Autodesk Fusion 360 part; units mm, degrees
(part 2 of 2)
sketch "Yellow connector plug sketch" plane through (0, 0, 3) normal (0, 0, 1) x (1, 0, 0) in component "14 Temperature sensor | Illustrative placement; probe detail pending"
  line L0 (102, 70) -> (114, 70)
  line L1 (114, 70) -> (114, 90)
  line L2 (114, 90) -> (102, 90)
  line L3 (102, 90) -> (102, 70)
extrude "Yellow connector plug" add sketch "Yellow connector plug sketch" along normal blind 6 separate body makes body 36 in component "14 Temperature sensor | Illustrative placement; probe detail pending"
ref_plane "WorkPlane5" through (0, 0, 4.5) normal (0, 0, 1) x (1, 0, 0) in component "14 Temperature sensor | Illustrative placement; probe detail pending"
sketch "Spade prongs sketch" plane through (0, 0, 4.5) normal (0, 0, 1) x (1, 0, 0) in component "14 Temperature sensor | Illustrative placement; probe detail pending"
  line L0 (104, 90) -> (106, 90)
  line L1 (106, 90) -> (106, 98)
  line L2 (106, 98) -> (104, 98)
  line L3 (104, 98) -> (104, 90)
  line L4 (110, 90) -> (112, 90)
  line L5 (112, 90) -> (112, 98)
  line L6 (112, 98) -> (110, 98)
  line L7 (110, 98) -> (110, 90)
extrude "Spade prongs" add sketch "Spade prongs sketch" along normal blind 3 bodies 36 in component "14 Temperature sensor | Illustrative placement; probe detail pending"
ref_plane "WorkPlane1" through (0, 0, -6.5) normal (0, 0, 1) x (1, 0, 0) in component "15 Lab test bench elevation standoffs & feet"
sketch "Leg_6_6 sketch" plane through (0, 0, -6.5) normal (0, 0, 1) x (1, 0, 0) in component "15 Lab test bench elevation standoffs & feet"
  circle A0 centre (6, 6) radius 4
extrude "Leg_6_6" add sketch "Leg_6_6 sketch" against normal blind 16 separate body makes body 37 in component "15 Lab test bench elevation standoffs & feet"
ref_plane "WorkPlane2" through (0, 0, -22.5) normal (0, 0, 1) x (1, 0, 0) in component "15 Lab test bench elevation standoffs & feet"
sketch "Foot_6_6 sketch" plane through (0, 0, -22.5) normal (0, 0, 1) x (1, 0, 0) in component "15 Lab test bench elevation standoffs & feet"
  circle A0 centre (6, 6) radius 6
extrude "Foot_6_6" add sketch "Foot_6_6 sketch" against normal blind 3 bodies 37 in component "15 Lab test bench elevation standoffs & feet"
ref_plane "WorkPlane3" through (0, 0, -6.5) normal (0, 0, 1) x (1, 0, 0) in component "15 Lab test bench elevation standoffs & feet"
sketch "Leg_74_6 sketch" plane through (0, 0, -6.5) normal (0, 0, 1) x (1, 0, 0) in component "15 Lab test bench elevation standoffs & feet"
  circle A0 centre (74, 6) radius 4
extrude "Leg_74_6" add sketch "Leg_74_6 sketch" against normal blind 16 separate body makes body 38 in component "15 Lab test bench elevation standoffs & feet"
ref_plane "WorkPlane4" through (0, 0, -22.5) normal (0, 0, 1) x (1, 0, 0) in component "15 Lab test bench elevation standoffs & feet"
sketch "Foot_74_6 sketch" plane through (0, 0, -22.5) normal (0, 0, 1) x (1, 0, 0) in component "15 Lab test bench elevation standoffs & feet"
  circle A0 centre (74, 6) radius 6
extrude "Foot_74_6" add sketch "Foot_74_6 sketch" against normal blind 3 bodies 38 in component "15 Lab test bench elevation standoffs & feet"
ref_plane "WorkPlane5" through (0, 0, -6.5) normal (0, 0, 1) x (1, 0, 0) in component "15 Lab test bench elevation standoffs & feet"
sketch "Leg_6_114 sketch" plane through (0, 0, -6.5) normal (0, 0, 1) x (1, 0, 0) in component "15 Lab test bench elevation standoffs & feet"
  circle A0 centre (6, 114) radius 4
extrude "Leg_6_114" add sketch "Leg_6_114 sketch" against normal blind 16 separate body makes body 39 in component "15 Lab test bench elevation standoffs & feet"
ref_plane "WorkPlane6" through (0, 0, -22.5) normal (0, 0, 1) x (1, 0, 0) in component "15 Lab test bench elevation standoffs & feet"
sketch "Foot_6_114 sketch" plane through (0, 0, -22.5) normal (0, 0, 1) x (1, 0, 0) in component "15 Lab test bench elevation standoffs & feet"
  circle A0 centre (6, 114) radius 6
extrude "Foot_6_114" add sketch "Foot_6_114 sketch" against normal blind 3 bodies 39 in component "15 Lab test bench elevation standoffs & feet"
ref_plane "WorkPlane7" through (0, 0, -6.5) normal (0, 0, 1) x (1, 0, 0) in component "15 Lab test bench elevation standoffs & feet"
sketch "Leg_74_114 sketch" plane through (0, 0, -6.5) normal (0, 0, 1) x (1, 0, 0) in component "15 Lab test bench elevation standoffs & feet"
  circle A0 centre (74, 114) radius 4
extrude "Leg_74_114" add sketch "Leg_74_114 sketch" against normal blind 16 separate body makes body 40 in component "15 Lab test bench elevation standoffs & feet"
ref_plane "WorkPlane8" through (0, 0, -22.5) normal (0, 0, 1) x (1, 0, 0) in component "15 Lab test bench elevation standoffs & feet"
sketch "Foot_74_114 sketch" plane through (0, 0, -22.5) normal (0, 0, 1) x (1, 0, 0) in component "15 Lab test bench elevation standoffs & feet"
  circle A0 centre (74, 114) radius 6
extrude "Foot_74_114" add sketch "Foot_74_114 sketch" against normal blind 3 bodies 40 in component "15 Lab test bench elevation standoffs & feet"
ref_plane "WorkPlane13" through (0, 0, 12) normal (0, 0, 1) x (1, 0, 0) in component "01 Cold plate | 6061-T6 Aluminium | 120 x 80 x 12 mm"
sketch "Sketch13" plane through (0, 0, 12) normal (0, 0, 1) x (1, 0, 0) in component "01 Cold plate | 6061-T6 Aluminium | 120 x 80 x 12 mm"
  circle A0 centre (40, 32) radius 2.1
  circle A1 centre (40, 88) radius 2.1
extrude "Reviewed blind mounting bores" cut sketch "Sketch13" against normal blind 4 bodies 1 in component "01 Cold plate | 6061-T6 Aluminium | 120 x 80 x 12 mm"
component "01 Cold plate | 6061-T6 Aluminium | 120 x 80 x 12 mm" placed x (1, 0, 0) y (0, 1, 0) z (0, 0, 1) at (0, 0, 0)
component "02 Perimeter sealing gasket | 0.5 mm silicone" placed x (1, 0, 0) y (0, 1, 0) z (0, 0, 1) at (0, 0, -15)
component "03 Bottom manifold cover | 6061-T6 Aluminium" placed x (1, 0, 0) y (0, 1, 0) z (0, 0, 1) at (0, 0, -30)
component "04 Inlet hose barb fitting | 6 mm bore" placed x (1, 0, 0) y (0, 1, 0) z (0, 0, 1) at (0, 0, 10)
component "05 Inlet anodized identification ring" placed x (1, 0, 0) y (0, 1, 0) z (0, 0, 1) at (0, 0, 10)
component "04 Outlet hose barb fitting | 6 mm bore" placed x (1, 0, 0) y (0, 1, 0) z (0, 0, 1) at (0, 0, 10)
component "05 Outlet anodized identification ring" placed x (1, 0, 0) y (0, 1, 0) z (0, 0, 1) at (0, 0, 10)
component "06 Thermal interface pad (TIM) | 0.2 mm" placed x (1, 0, 0) y (0, 1, 0) z (0, 0, 1) at (0, 0, 30)
component "07 SCR baseplate | Generic envelope 68 x 22 x 3.5 mm" placed x (1, 0, 0) y (0, 1, 0) z (0, 0, 1) at (0, 0, 30)
component "08 Thyristor housing | Generic academic envelope" placed x (1, 0, 0) y (0, 1, 0) z (0, 0, 1) at (0, 0, 30)
component "09 Power terminals | Copper pads & M6 Brass studs" placed x (1, 0, 0) y (0, 1, 0) z (0, 0, 1) at (0, 0, 30)
component "10 Gate & auxiliary trigger terminals" placed x (1, 0, 0) y (0, 1, 0) z (0, 0, 1) at (0, 0, 30)
component "11 SCR M5 socket head cap screws" placed x (1, 0, 0) y (0, 1, 0) z (0, 0, 1) at (0, 0, 30)
component "12 Cover perimeter bolts | 8x M4 socket cap screws" placed x (1, 0, 0) y (0, 1, 0) z (0, 0, 1) at (0, 0, 20)
component "13 Cover nuts | 8x M4 hex nuts" placed x (1, 0, 0) y (0, 1, 0) z (0, 0, 1) at (0, 0, -29.5)
component "14 Temperature sensor | Illustrative placement; probe detail pending" placed x (1, 0, 0) y (0, 1, 0) z (0, 0, 1) at (0, 0, 0)
component "15 Lab test bench elevation standoffs & feet" placed x (1, 0, 0) y (0, 1, 0) z (0, 0, 1) at (0, 0, -29.5)
equation "d459 = -( 7 mm )"
equation "d463 = -( 12 mm )"
equation "d475 = -( 0.5 mm )"
equation "d479 = -( 0.5 mm )"
equation "d483 = -( 6.0 mm )"
equation "d487 = -( 6.0 mm )"
equation "d503 = -( 16.0 mm )"
equation "d529 = -( 16.0 mm )"
equation "d687 = -( 3.0 mm )"
equation "d691 = -( 3.0 mm )"
equation "d695 = -( 3.0 mm )"
equation "d699 = -( 3.0 mm )"
equation "d703 = -( 3.0 mm )"
equation "d707 = -( 3.0 mm )"
equation "d711 = -( 3.0 mm )"
equation "d715 = -( 3.0 mm )"
equation "d719 = -( 3.0 mm )"
equation "d723 = -( 3.0 mm )"
equation "d727 = -( 3.0 mm )"
equation "d731 = -( 3.0 mm )"
equation "d735 = -( 3.0 mm )"
equation "d739 = -( 3.0 mm )"
equation "d743 = -( 3.0 mm )"
equation "d747 = -( 3.0 mm )"
equation "d771 = -( 16.0 mm )"
equation "d775 = -( 3.0 mm )"
equation "d779 = -( 16.0 mm )"
equation "d783 = -( 3.0 mm )"
equation "d787 = -( 16.0 mm )"
equation "d791 = -( 3.0 mm )"
equation "d795 = -( 16.0 mm )"
equation "d799 = -( 3.0 mm )"
equation "d803 = -( 4.00 mm )"
